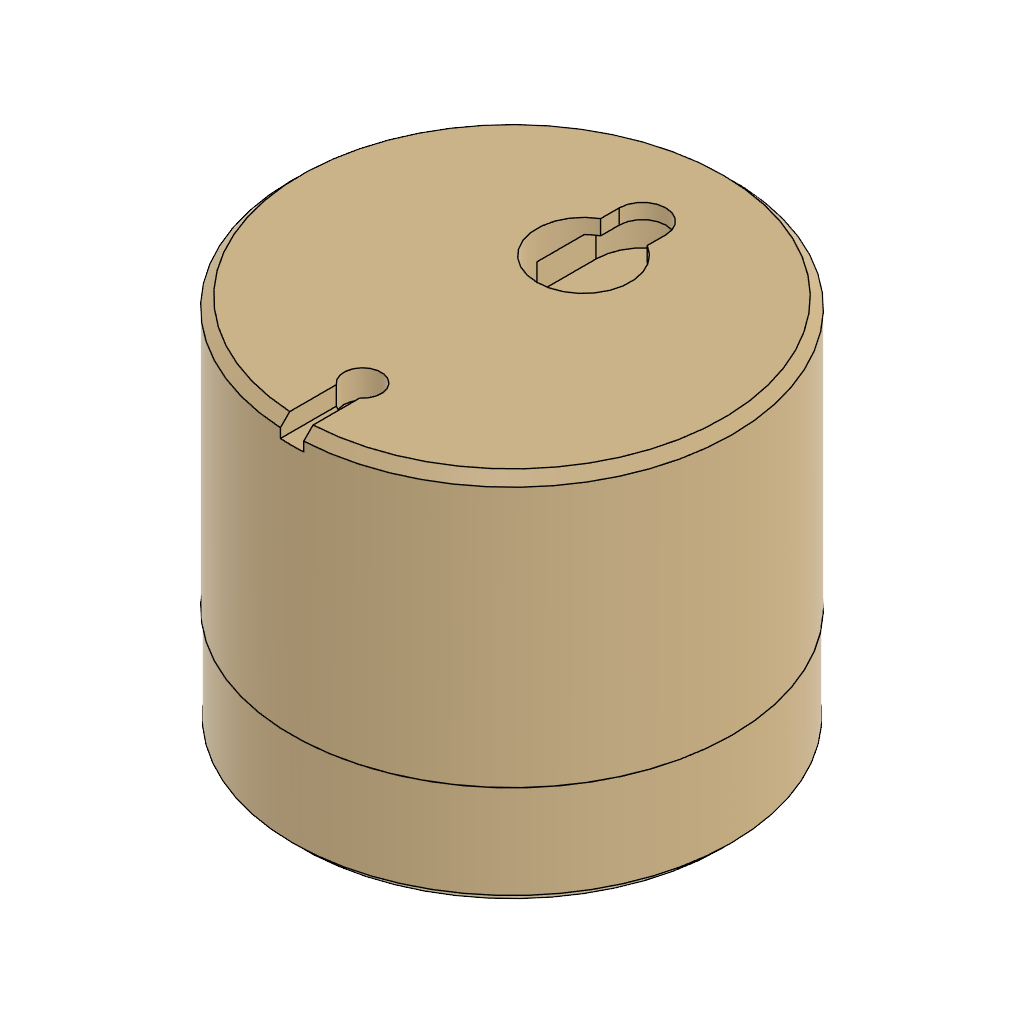
Spk 40mm Faceplate (Autodesk Fusion 360 design; units mm, degrees)
Autodesk Fusion 360 part; units mm, degrees
sketch "Sketch1" plane through (0, 0, 0) normal (0, 0, 1) x (1, 0, 0)
  circle A0 centre (0, 0) radius 20.2
  circle A1 centre (0, 0) radius 21.85
  circle A2 centre (0, 0) radius 4
  circle A3 centre (0, 0) radius 7.638
  circle A4 centre (0, 0) radius 18.55
  circle A5 centre (0, 0) radius 23.5
  dimension "d1" = 40.4
  dimension "d2" = 1.65
  dimension "d4" = 8
  dimension "d6" = 1.65
  dimension "d13" = 1.65
  constraint coincident A0.centre A1.centre
  constraint concentric A0 A1
  constraint concentric A0 A2
  constraint concentric A1 A3
  constraint concentric A2 A4
  constraint concentric A1 A5
  measures "d1" diameter of A0
  measures "d2" distance of A0 A1
  measures "d4" diameter of A2
  measures "d6" distance of A0 A4
  measures "d13" distance of A1 A5
extrude "Extrude1" add sketch "Sketch1" against normal blind 2 contours A0 | A1 | A2 | A5 makes body 1 at (21.7625, -1.1675, 0) makes body 2 at (3.995, -0.1994, -1.3333)
extrude "Extrude2" cut 1 faces at (-1.2456, 0.0132, 0) along direction (0, 0, -1) blind 1 on bodies 2 bodies 2
extrude "Extrude3" add sketch "Sketch1" along normal blind 12.5 contours A1 bodies 1
extrude "Extrude4" add sketch "Sketch1" along normal blind 9 contours A5 bodies 1
sketch "Sketch2" plane through (0, 0, -1) normal (0, 0, 1) x (-1, 0, 0)
  circle A0 centre (0, 0) radius 4
  circle A1 centre (0, 0) radius 7.75
  circle A2 centre (0, 0) radius 9.4
  circle A3 centre (0, 0) radius 13.15
  circle A4 centre (0, 0) radius 14.8
  circle A5 centre (0, 0) radius 18.55
  line L0 (0.825, -3.914) -> (0.825, -18.5316)
  line L1 (-0.825, -18.5316) -> (-0.825, -3.914)
  line L2 (0, 0) -> (0, -18.55) construction
  line L3 (3.8021, -1.2425) -> (16.4614, -8.5514)
  line L4 (15.6364, -9.9803) -> (2.9771, -2.6715)
  line L5 (2.9771, 2.6715) -> (15.6364, 9.9803)
  line L6 (16.4614, 8.5514) -> (3.8021, 1.2425)
  line L7 (-0.825, 3.914) -> (-0.825, 18.5316)
  line L8 (0.825, 18.5316) -> (0.825, 3.914)
  line L9 (-3.8021, 1.2425) -> (-16.4614, 8.5514)
  line L10 (-15.6364, 9.9803) -> (-2.9771, 2.6715)
  line L11 (-2.9771, -2.6715) -> (-15.6364, -9.9803)
  line L12 (-16.4614, -8.5514) -> (-3.8021, -1.2425)
  dimension "d17" = 1.65
  dimension "d18" = 1.65
  dimension "d19" = 3.75
  dimension "d20" = 3.75
  dimension "d21" = 1.65
  dimension "d23" = 360
  constraint coincident A0.centre A1.centre
  constraint concentric A2 A3
  constraint concentric A2 A4
  constraint coincident A0 L0.start
  constraint coincident A5 L0.end
  constraint vertical L0
  constraint coincident A5 L1.start
  constraint coincident A0 L1.end
  constraint parallel L0 L1
  constraint coincident A5 L2.end
  constraint vertical L2
  measures "d17" distance of A3 A4
  measures "d18" distance of A1 A2
  measures "d19" distance of A2 A3
  measures "d20" distance of A0 A1
  measures "d21" distance of L0 L1
extrude "Extrude5" add sketch "Sketch2" 1 faces at (-1.2456, 0.0132, -1) against normal blind 1 contours A0 | A0 A1 L5 L6 | A0 A1 L3 L4 | A1 A2 L3 L6 | A1 A2 L5 L6 | A1 A2 L3 L4 | A0 A1 L7 L8 | A1 A2 L5 L8 | A2 A3 L5 L6 | A0 A1 L0 L1 | A1 A2 L0 L4 | A2 A3 L3 L4 | A1 A2 L7 L8 | A3 A4 L3 L6 | A3 A4 L5 L6 | A1 A2 L0 L1 | A3 A4 L3 L4 | A0 A1 L9 L10 | A1 A2 L7 L10 | A2 A3 L7 L8 | A3 A4 L5 L8 | A4 A5 L5 L6 | A0 A1 L11 L12 | A1 A2 L1 L11 | A2 A3 L0 L1 | A3 A4 L0 L4 | A4 A5 L3 L4 | A1 A2 L9 L10 | A3 A4 L7 L8 | A1 A2 L11 L12 | A3 A4 L0 L1 | A1 A2 L9 L12 | A2 A3 L9 L10 | A3 A4 L7 L10 | A4 A5 L7 L8 | A2 A3 L11 L12 | A3 A4 L1 L11 | A4 A5 L0 L1 | A3 A4 L9 L10 | A3 A4 L11 L12 | A3 A4 L9 L12 | A4 A5 L9 L10 | A4 A5 L11 L12 on bodies 2 bodies 1 2
chamfer "Chamfer1" distance 0.4 angle 45 2 edges at (-20.3714, -7.9013, 12.5) (-18.833, 7.3046, 12.5) tangent chain off on bodies 1
sketch "Sketch3" plane through (0, 0, 0) normal (0, 1, 0) x (1, 0, 0)
  line L0 (-21.85, -9) -> (21.85, -9)
  line L1 (-21.85, -12.1) -> (21.85, -12.1)
  line L2 (-21.85, -12.1) -> (21.85, -12.1)
  line L3 (21.45, -12.5) -> (-21.45, -12.5)
  line L4 (-23.5, -9) -> (23.5, -9)
  line L5 (23.5, 2) -> (-23.5, 2)
  line L6 (23.62, -9.1) -> (21.97, -9.1)
  line L7 (21.97, -9.1) -> (21.97, -36)
  line L8 (23.62, -9.1) -> (23.62, -38)
  line L9 (23.62, -38) -> (0, -38)
  line L10 (0, -38) -> (0, -36)
  line L11 (0, -36) -> (21.97, -36)
  line L12 (0, 0) -> (0, -36) construction
  dimension "d27" = 1.65
  dimension "d28" = 0.12
  dimension "d29" = 0.1
  dimension "d30" = 40
  dimension "d31" = 2
  constraint parallel L4 L6
  constraint perpendicular L6 L7
  constraint perpendicular L6 L8
  constraint perpendicular L8 L9
  constraint perpendicular L9 L10
  constraint perpendicular L10 L11
  constraint coincident L7.end L11.end
  constraint coincident L12.start origin
  constraint vertical L12
  measures "d27" distance of L6.start L6.end
  measures "d28" distance of L0.end L7
  measures "d29" distance of L0.end L6
  measures "d30" vertical distance of L5.start L8.end
  measures "d31" distance of L9.end L10.end
revolve "Revolve1" add sketch "Sketch3" angle 360 about axis through (0, 0, 38) along (0, 0, -1) separate body makes body 3
chamfer "Chamfer2" distance 0.4 angle 45 1 edges at (-20.4832, -7.9447, 9.1) tangent chain off on bodies 3
sketch "Sketch4" plane through (0, 0, 38) normal (0, 0, 1) x (-1, 0, 0)
  circle A0 centre (0, 0) radius 23.62
  line L0 (0, -28.1427) -> (0, 0) construction
  arc A1 (-7, -14) -> (7, -14) centre (0, -14) ccw
  line L1 (7, -14) -> (7, -7.6699)
  arc A2 (7, -7.6699) -> (-7, -7.6699) centre (0, -7.6699) ccw
  line L2 (-7, -7.6699) -> (-7, -14)
  line L3 (2.5, -12) -> (2.5, -14)
  arc A3 (-2.5, -14) -> (2.5, -14) centre (0, -14) ccw
  line L4 (-2.5, -14) -> (-2.5, -12)
  arc A4 (2.5, -12) -> (-2.5, -12) centre (0, -7.6699) ccw
  line L5 (-5, -7.6699) -> (-5, -14)
  arc A5 (-5, -14) -> (5, -14) centre (0, -14) ccw
  line L6 (5, -14) -> (5, -7.6699)
  line L7 (0, 0) -> (0, 16.0257) construction
  circle A6 centre (0, 16.0257) radius 2
  line L8 (1.25, 17.5869) -> (1.25, 23.5869)
  line L9 (-1.25, 17.5869) -> (-1.25, 23.5869)
  line L10 (2.9, 23.4413) -> (2.9, 16.0257)
  arc A7 (-2.9, 16.0257) -> (2.9, 16.0257) centre (0, 16.0257) ccw
  line L11 (-2.9, 16.0257) -> (-2.9, 23.4413)
  dimension "d41" = 2.5
  dimension "d42" = 5
  dimension "d43" = 2
  dimension "d45" = 2
  dimension "d46" = 2
  dimension "d47" = 14
  dimension "d48" = 2.5
  dimension "d49" = 4
  dimension "d50" = 6
  dimension "d52" = 1.65
  constraint coincident A0.centre L0.end
  constraint vertical L0
  constraint vertical L1
  constraint tangent L1 A2
  constraint vertical L2
  constraint tangent A2 L2
  constraint coincident L0 A2.centre
  constraint tangent A1 L1
  constraint parallel L0 L3
  constraint tangent L3 A3
  constraint tangent A3 L4
  constraint parallel L3 L4
  constraint tangent A1 L2
  constraint coincident A2.centre A4.centre
  constraint coincident A4 L5.start
  constraint vertical L5
  constraint tangent L5 A5
  constraint coincident A4 L6.end
  constraint tangent A4 L6
  constraint vertical L6
  constraint tangent A5 L6
  constraint coincident A1.centre A3.centre
  constraint parallel L0 L7
  constraint coincident L7.end A6.centre
  constraint coincident A6 L8.start
  constraint coincident A0 L8.end
  constraint vertical L8
  constraint coincident A6 L9.start
  constraint coincident A0 L9.end
  constraint parallel L8 L9
  constraint symmetric L7 L8 L9
  constraint coincident A0 L10.start
  constraint parallel L8 L10
  constraint tangent L10 A7
  constraint coincident A0 L11.end
  constraint tangent A7 L11
  constraint parallel L7 L11
  measures "d41" radius of A3
  measures "d42" radius of A4
  measures "d43" distance of A2 A4
  measures "d45" distance of A1 A5
  measures "d46" distance of L3.start L3.end
  measures "d47" distance of A0.centre A1.centre
  measures "d48" distance of L8 L9
  measures "d49" diameter of A6
  measures "d50" distance of L8.start L8.end
  measures "d52" distance of L8 L10
extrude "Extrude6" add sketch "Sketch4" against normal blind 4 contours A0 A6 L8 L9 L10 A7 L11 | A0 A6 L8 L9 | A6 bodies 3
extrude "Extrude7" cut sketch "Sketch4" against normal blind 4 contours A6 bodies 3
extrude "Extrude8" cut sketch "Sketch4" against normal blind 2 contours A0 A6 L8 L9 bodies 3
extrude "Extrude9" cut sketch "Sketch4" against normal blind 1.6 contours L3 A3 L4 A4 bodies 3
extrude "Extrude10" cut sketch "Sketch4" against normal blind 3 from surface at -1.6 contours L3 A3 L4 A4 L5 A5 L6 | L3 A3 L4 A4 bodies 3
extrude "Extrude11" add sketch "Sketch4" against normal blind 6 contours A1 L1 A2 L2 bodies 3
extrude "Extrude12" add sketch "Sketch4" against normal blind 2 from surface at -6 contours A1 L1 A2 L2 | L3 A3 L4 A4 L5 A5 L6 | L3 A3 L4 A4 bodies 3
chamfer "Chamfer3" distance 0.5 angle 45 14 edges at (0, 0.6699, 30) (-7, 10.8349, 30) (0, 21, 30) (7, 10.8349, 30) (0, 0.6699, 36) (7, 10.8349, 36) (0, 21, 36) (-7, 10.8349, 36) (-2.9, -18.9017, 36) (2.9, -18.9017, 36) (0, -13.1257, 36) (-2.9, -18.9017, 34) (0, -13.1257, 34) (2.9, -18.9017, 34) tangent chain off on bodies 3
fillet "Fillet1" radius 1 1 edges at (1.8647, -15.3024, 34) on bodies 3
chamfer "Chamfer4" distance 1.5 angle 45 3 edges at (-5, 10.8349, 36.4) (0, 19, 36.4) (5, 10.8349, 36.4) tangent chain off on bodies 3
chamfer "Chamfer5" distance 1 angle 45 2 edges at (-21.9097, 8.498, -2) (0, 23.62, 38) tangent chain off on bodies 1 3
